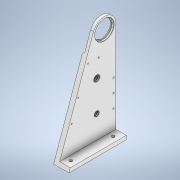
# Autodesk Inventor part: 1.1_2_SideArmClose
Saved by Autodesk Inventor 2021 (Build 250183000, 183)
## iProperties
Created: 2025-11-05
Part Number: 1.1_2_SideArmClose
Material: ABS Plastic
Document SubType Name: Modeling
Designer: Admin
Density: 1.06 g/cm^3
Appearance: Smooth - White
Mass: 2955.69 g
Surface Area: 2973.3 cm^2
Volume: 2788.39 cm^3
Author: Admin
Autodesk Inventor part; units mm, degrees
ref_plane "YZ Plane" through (0, 0, 0) normal (1, 0, 0) x (0, 1, 0)
ref_plane "XY Plane" through (0, 0, 0) normal (0, 0, 1) x (1, 0, 0)
sketch "Sketch2" plane through (0, 0, 0) normal (1, 0, 0) x (0, 1, 0)
  line L0 (0, 0) -> (-500, 0)
  dimension "d6" = 500
  constraints: 2 end point, 1 horizontal
  measures "d6" distance of L0.start L0.end
sketch "Sketch1" plane through (0, 0, 0) normal (0, 0, 1) x (1, 0, 0)
  line L0 (0, 50) -> (10, 50)
  line L1 (10, 50) -> (10, 46)
  line L2 (10, 46) -> (15, 46)
  line L3 (15, 46) -> (15, 60)
  line L4 (15, 60) -> (0, 60)
  line L5 (0, 60) -> (0, 50)
  line L6 (-3, 0) -> (18, 0) projected
  line L7 (0, -612) -> (0, 172) projected
  point P0 (0, 0)
  dimension "d0" = 60
  dimension "d1" = 50
  dimension "d2" = 5
  dimension "d3" = 10
  dimension "d4" = 4
  constraints: 13 end point, 5 perpendicular, 1 collinear, 1 horizontal
  measures "d0" distance between parallel lines of L6 L4
  measures "d1" distance between parallel lines of L6 L0
  measures "d2" distance of L1.end L2.end
  measures "d3" distance of L0.start L0.end
  measures "d4" distance between parallel lines of L2 L0
revolve "Revolution1" add sketch "Sketch1" angle 360 about axis through (0, 0, 0) along (1, 0, 0)
sketch "Sketch3" plane through (0, 0, 0) normal (1, 0, 0) x (0, 1, 0)
  circle A0 centre (0, 0) radius 60 projected
  line L0 (19.9597, 56.5828) -> (-500, 240)
  line L1 (-500, 240) -> (-500, -60)
  line L2 (-500, -60) -> (0, -60)
  arc A1 (19.9597, 56.5828) -> (0, -60) centre (0, 0) ccw
  point P0 (0, -60)
  dimension "d10" = 500
  dimension "d11" = 300
  constraints: 6 end point, 2 horizontal, 2 point on circle, 1 centre point, 1 coincident, 1 vertical, 3 other
  measures "d10" distance of L1.end L2.end
  measures "d11" distance of L0.end L1.end
extrude "Extrusion1" add sketch "Sketch3" along normal up to surface (15 mm away) contours A0 L2 L1 L0
sketch "Sketch4" plane through (0, 0, 0) normal (1, 0, 0) x (0, 1, 0)
  line L0 (-500, -60) -> (0, -60) projected
  line L1 (-490, -60) -> (-290, -60)
  line L2 (-290, -60) -> (-290, -35)
  line L3 (-290, -35) -> (-490, -35)
  line L4 (-490, -35) -> (-490, -60)
  line L5 (-500, 240) -> (-500, -60) projected
  line L6 (-83.1215, 0) -> (-103.1215, 0)
  line L7 (-103.1215, 0) -> (-103.1215, 100)
  line L8 (19.9597, 56.5828) -> (-500, 240) projected
  line L9 (-83.1215, 92.9449) -> (-83.1215, 0)
  line L10 (-103.1215, 100) -> (-83.1215, 92.9449)
  line L11 (-603.9919, 0) -> (123.9517, 0) projected
  point P0 (0, 0)
  dimension "d12" = 200
  dimension "d13" = 10
  dimension "d14" = 25
  dimension "d15" = 20
  dimension "d16" = 100
  constraints: 16 end point, 3 perpendicular, 3 point on line, 2 horizontal, 2 parallel, 1 collinear
  measures "d12" distance between parallel lines of L2 L4
  measures "d13" distance between parallel lines of L5 L4
  measures "d14" distance of L1.end L2.end
  measures "d15" distance between parallel lines of L9 L7
  measures "d16" distance of L6.end L7.end
extrude "Extrusion2" [suppressed]
sketch "Sketch5" plane through (0, 0, 0) normal (1, 0, 0) x (0, 1, 0)
  circle A0 centre (-410, 140) radius 60 construction
  line L0 (-500, 240) -> (-500, -60) projected
  line L1 (-600, 0) -> (100, 0) projected
  line L2 (-360, 40) -> (-178.1459, 40) construction
  point P0 (0, 0)
  point P1 (-300, 115)
  point P2 (-200, 40)
  dimension "d19" = 120
  dimension "d20" = 90
  dimension "d21" = 140
  dimension "d22" = 100
  dimension "d23" = 140
  dimension "d24" = 200
  dimension "d25" = 300
  dimension "d26" = 75
  constraints: 2 end point, 1 centre point, 1 coincident, 1 horizontal, 1 point on line
  measures "d19" diameter of A0
  measures "d20" distance from line of L0 point (-410, 140)
  measures "d21" distance from line of L1 point (-410, 140)
  measures "d22" vertical distance of L2.start point (-410, 140)
  measures "d23" distance from line of L0 L2.start
  measures "d24" distance from line of L0 point (-300, 115)
  measures "d25" distance from line of L0 point (-200, 40)
  measures "d26" distance from line of point (-300, 115) L2
mirror "Mirror2" about plane through (0, 0, 0) normal (1, 0, 0) remove original yes
sketch "Sketch6" plane through (-15, -500, -60) normal (-1, 0, 0) x (0, 0, 1)
  line L0 (0, 0) -> (300, 0)
  line L1 (300, 0) -> (0, 0) projected
  line L2 (0, 0) -> (300, 0)
  line L3 (300, 0) -> (150.0801, 425)
  line L4 (116.5828, 519.9597) -> (300, 0) projected
  line L5 (150.0801, 425) -> (0, 300)
  line L6 (0, 0) -> (0, 500) projected
  line L7 (0, 0) -> (0, 300)
  point P0 (60, 500)
  dimension "d33" = 425
  dimension "d34" = 300
  constraints: 10 end point, 2 horizontal, 2 point on line, 1 perpendicular
  measures "d33" distance from line of L0 L3.end
  measures "d34" distance from line of L0 L5.end
extrude "Extrusion3" add sketch "Sketch6" along normal blind 10
chamfer "Chamfer1" distance 10 angle 45 1 edges at (-15, -137.5, 15.04)
ref_plane "Work Plane1" through (0, -200, 40) normal (0, 1, 0) x (-1, 0, 0)
sketch "Sketch7" plane through (0, -200, 40) normal (0, 1, 0) x (-1, 0, 0)
  line L0 (0, 200) -> (0, -100) projected
  line L1 (25, 0) -> (0, 0)
  line L2 (0, 0) -> (0, 15)
  line L3 (0, 15) -> (7, 15)
  line L4 (7, 15) -> (7, 13)
  line L5 (7, 13) -> (25, 13)
  line L6 (25, 13) -> (25, 0)
  line L7 (25, -100) -> (25, 200) projected
  line L8 (-22.8, 0) -> (31.8, 0) projected
  point P0 (0, -40)
  point P1 (0, 0)
  dimension "d36" = 15
  dimension "d37" = 2
  dimension "d38" = 7
  constraints: 12 end point, 5 perpendicular, 3 collinear, 1 horizontal
  measures "d36" distance between parallel lines of L1 L3
  measures "d37" distance of L3.end L4.end
  measures "d38" distance of L2.end L3.end
revolve "Revolution2" cut sketch "Sketch7" angle 360 about axis through (-25, -200, 40) along (1, 0, 0)
sketch "Sketch8" plane through (0, -500, -60) normal (1, 0, 0) x (0, 0, -1)
  line L0 (-116.5828, 519.9597) -> (-300, 0) projected
  line L1 (-300, 0) -> (-292.9449, 20)
  line L2 (-292.9449, 20) -> (0, 20)
  line L3 (0, 0) -> (0, 500) projected
  line L4 (0, 20) -> (0, 0)
  line L5 (0, 0) -> (-300, 0)
  point P0 (-60, 500)
  dimension "d40" = 20
  constraints: 8 end point, 2 point on line, 1 horizontal, 1 perpendicular, 1 vertical
  measures "d40" distance between parallel lines of L5 L2
extrude "Extrusion4" add sketch "Sketch8" along normal blind 55
ref_plane "Work Plane3" through (0, -360, 40) normal (0, 1, 0) x (-1, 0, 0)
ref_plane "Work Plane2" through (67, -510, 91) normal (0, 1, 0) x (-1, 0, 0)
sketch "Sketch9" plane through (0, -360, 40) normal (0, 1, 0) x (-1, 0, 0)
  line L0 (25, -100) -> (25, 200) projected
  line L1 (25, 0) -> (0, 0)
  line L2 (0, 192.9449) -> (0, -100) projected
  line L3 (0, 0) -> (0, -12)
  line L4 (0, -12) -> (8, -12)
  line L5 (8, -12) -> (8, -11)
  line L6 (8, -11) -> (25, -11)
  line L7 (25, -11) -> (25, 0)
  line L8 (-22.8, 0) -> (31.8, 0) projected
  point P0 (0, -40)
  point P1 (25, -11)
  point P2 (0, -12)
  dimension "d44" = 8
  dimension "d45" = 12
  dimension "d46" = 1
  constraints: 12 end point, 4 perpendicular, 2 point on line, 1 collinear, 1 horizontal, 1 vertical
  measures "d44" distance of L3.end L4.end
  measures "d45" distance between parallel lines of L1 L4
  measures "d46" distance of L4.end L5.end
revolve "Revolution3" cut sketch "Sketch9" angle 360 about axis through (-25, -360, 40) along (1, 0, 0)
sketch "Sketch10" plane through (-25, -500, -60) normal (-1, 0, 0) x (0, 0, 1)
  line L0 (0, 0) -> (300, 0) projected
  line L1 (145, 390) -> (-34.7845, 390)
  line L2 (188.6218, 280.3045) -> (250.648, 104.4698)
  line L3 (300, 0) -> (150.0801, 425) projected
  line L4 (0, 500) -> (0, 313.0142) projected
  line L5 (12.5, 260) -> (12.5, 67.2514)
  line L6 (0, 300) -> (0, 0) projected
  line L7 (188.6218, 280.3045) -> (201.1218, 280.3045)
  point P0 (60, 500)
  point P1 (195.7843, 260)
  point P2 (231.0596, 160)
  point P3 (90, 390)
  point P4 (12.5, 190)
  point P5 (12.5, 120)
  dimension "d48" = 55
  dimension "d49" = 390
  dimension "d50" = 260
  dimension "d51" = 160
  dimension "d53" = 145
  dimension "d54" = 12.5
  dimension "d55" = 260
  dimension "d56" = 120
  dimension "d57" = 70
  dimension "d65" = 12.5
  constraints: 8 end point, 6 point on line, 2 horizontal, 1 parallel, 1 vertical
  measures "d48" distance of L1.start point (90, 390)
  measures "d49" distance from line of L0 L1.start
  measures "d50" distance from line of L0 point (195.784, 260)
  measures "d51" distance from line of L0 point (231.06, 160)
  measures "d53" distance from line of L4 L1.start
  measures "d54" distance between parallel lines of L6 L5
  measures "d55" distance from line of L0 L5.start
  measures "d56" distance from line of point (12.5, 120) L0
  measures "d57" distance of point (12.5, 120) point (12.5, 190)
  measures "d65" distance of L2.start L7.end
hole "Hole1" at (-25, -240, -47.5) at (-25, -310, -47.5) at (-25, -380, -47.5) at (-25, -110, 30) at (-25, -110, 85) at (-25, -240, 135.7843) at (-25, -340, 171.0596) direction (1, 0, 0) diameter 6.6 end through all counterbore diameter 10 counterbore depth 10
sketch "Sketch11" plane through (0, -480, 232.9449) normal (0, 1, 0) x (1, 0, 0)
  line L0 (0, 292.9449) -> (55, 292.9449) projected
  line L1 (-25, -7.0551) -> (55, -7.0551) projected
  line L2 (-25, -7.0551) -> (-25, 142.8649) projected
  line L3 (-25, 142.8649) -> (-25, 292.9449) projected
  point P0 (0, 232.9449)
  point P1 (25, 252.9449)
  point P2 (25, 32.9449)
  dimension "d66" = 40
  dimension "d67" = 40
  dimension "d68" = 50
  dimension "d69" = 50
  measures "d66" distance from line of L0 point (25, 252.945)
  measures "d67" distance from line of L1 point (25, 32.945)
  measures "d68" distance from line of L2 point (25, 32.945)
  measures "d69" distance from line of L3 point (25, 252.945)
hole "Hole2" at (25, -480, -20) at (25, -480, 200) direction (0, -1, 0) diameter 9 end through all counterbore diameter 15 counterbore depth 8 clearance for "Socket Head Cap Screw ISO 4762" size "M8" standard "ISO"
fillet "Fillet1" radius 0.2 1 edges at (-7, -200, 25)
fillet "Fillet2" radius 0.2 1 edges at (-8, -360, 52)
fillet "Fillet4" radius 0.4 1 edges at (-10, -50, 0)
chamfer "Chamfer3" distance 1 angle 45 6 edges at (0, -50, 0) (-15, -46, 0) (0, -200, 25) (0, -360, 52) (-25, -200, 27) (-25, -360, 51)
equation "\"d10\" = d6"
body "Solid1"
